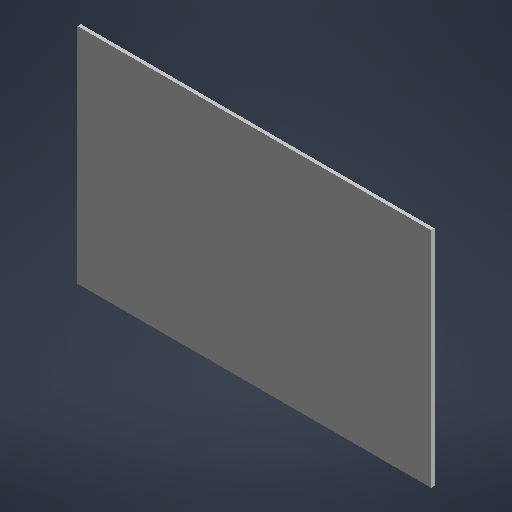
# Autodesk Inventor part: RFID_Card
Saved by Autodesk Inventor 2027.1 (Build 311270010, 270A)
## iProperties
Part Number: RFID_Card
Material: Generic
Document SubType Name: Modeling
Designer: austin
Appearance: Smooth - White
Author: austin
Autodesk Inventor part; units mm, degrees
ref_plane "YZ Plane" through (0, 0, 0) normal (1, 0, 0) x (0, 1, 0)
ref_plane "XZ Plane" through (0, 0, 0) normal (0, 1, 0) x (-1, 0, 0)
ref_plane "XY Plane" through (0, 0, 0) normal (0, 0, 1) x (1, 0, 0)
sketch "Sketch1" plane through (0, 0, 0) normal (0, 0, 1) x (1, 0, 0)
  line L0 (-42.8, -27) -> (42.8, -27)
  line L1 (42.8, -27) -> (42.8, 27)
  line L2 (42.8, 27) -> (-42.8, 27)
  line L3 (-42.8, 27) -> (-42.8, -27)
  constraints: 8 end point, 2 parallel, 1 horizontal, 1 perpendicular
extrude "Extrusion1" add sketch "Sketch1" along normal blind 0.82
body "Solid1"
